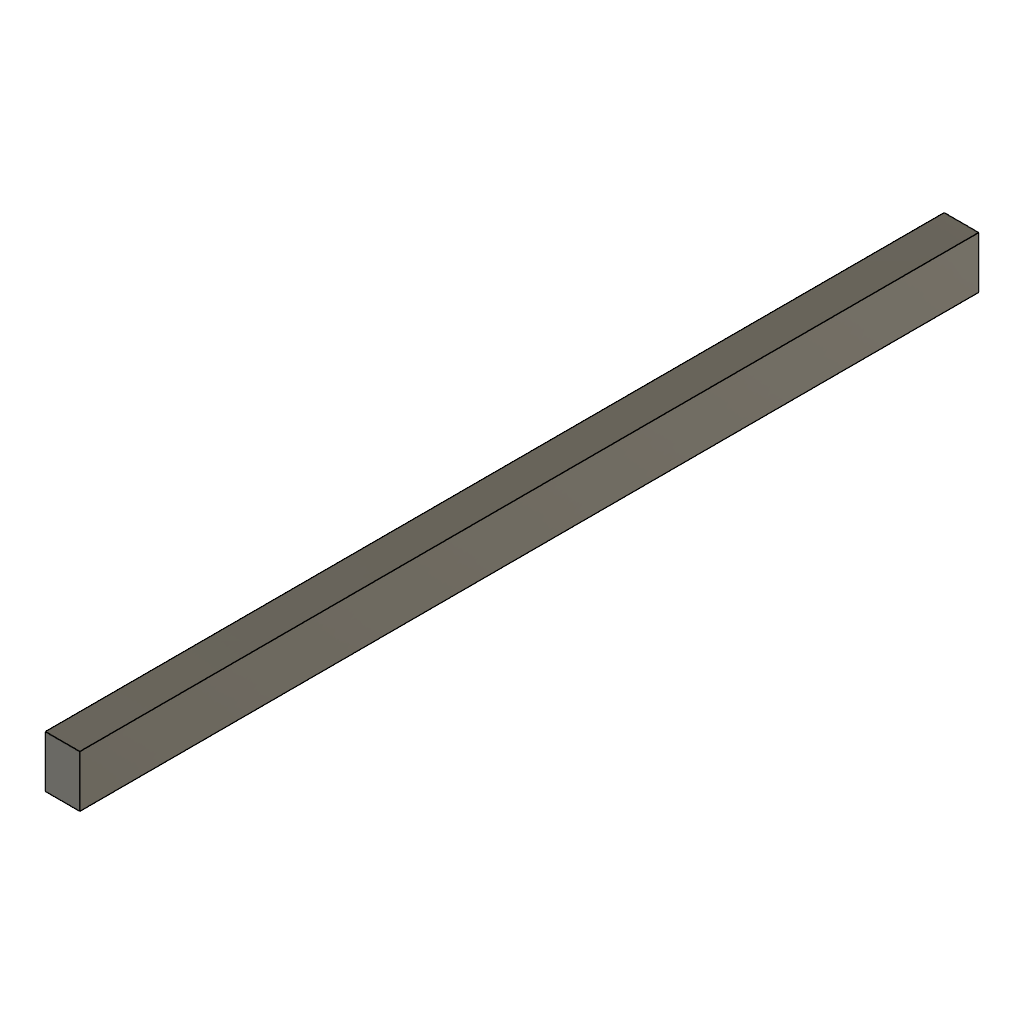
Fox Head Timing Belt Housing (Autodesk Fusion 360 archive; units mm, degrees)
design "side piece lock V2 (smaller)"
part number: 2026-11-04-11-16-01-376
Autodesk Fusion 360 part; units mm, degrees
sketch "Sketch1" plane through (0, 0, 0) normal (1, 0, 0) x (0, 1, 0)
  line L0 (0, 0) -> (104, 0)
  line L1 (104, 0) -> (104, 6)
  line L2 (104, 6) -> (0, 6)
  line L3 (0, 6) -> (0, 0)
  dimension "d1" = 6
  dimension "d2" = 104
  constraint horizontal L0
  constraint vertical L1
  constraint horizontal L2
  constraint vertical L3
  constraint coincident L0.start L3.end
  measures "d1" distance of L0.start L2.end
  measures "d2" distance of L1.end L2.end
extrude "Extrude1" add sketch "Sketch1" along normal blind 4
equation "d4 = 0deg 0'"

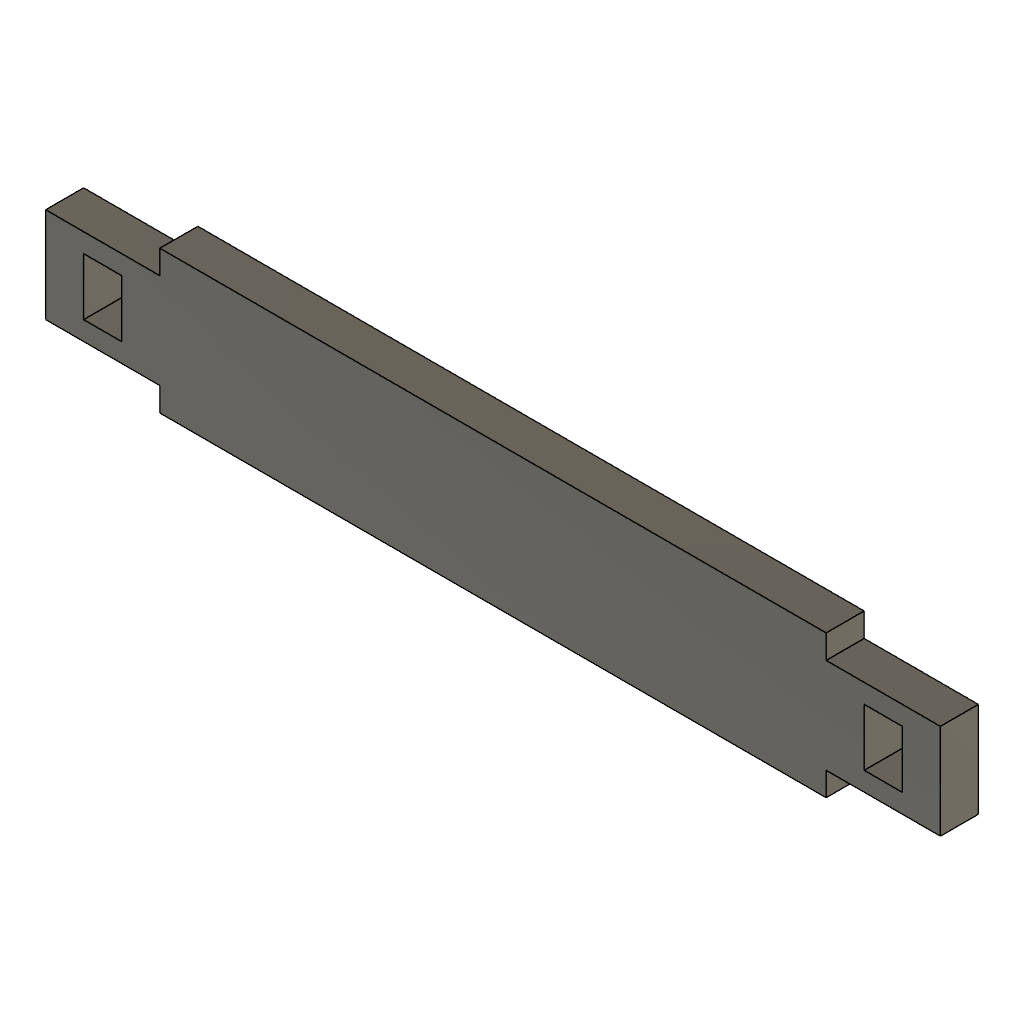
design "side piece connectors v2"
part number: 2026-11-04-10-45-29-765
Autodesk Fusion 360 part; units mm, degrees
sketch "Sketch1" plane through (0, 0, 0) normal (0, 1, 0) x (1, 0, 0)
  line L0 (12, -12.5) -> (82, -12.5)
  line L1 (82, 2.5) -> (12, 2.5)
  line L2 (12, -10) -> (0, -10)
  line L3 (0, -10) -> (0, 0)
  line L4 (0, 0) -> (12, 0)
  line L5 (4, -2) -> (8, -2)
  line L6 (8, -2) -> (8, -8)
  line L7 (8, -8) -> (4, -8)
  line L8 (4, -8) -> (4, -2)
  line L9 (82, -10) -> (94, -10)
  line L10 (86, -8) -> (90, -8)
  line L11 (90, -2) -> (86, -2)
  line L12 (86, -2) -> (86, -8)
  line L13 (90, -8) -> (90, -2)
  line L14 (94, -10) -> (94, 0)
  line L15 (94, 0) -> (82, 0)
  line L16 (12, 2.5) -> (12, 0)
  line L17 (12, -10) -> (12, -12.5)
  line L18 (82, -12.5) -> (82, -10)
  line L19 (82, 0) -> (82, 2.5)
  point P0 (4, -5)
  point P1 (94, -5)
  point P2 (90, -5)
  point P3 (94, 0)
  dimension "d1" = 70
  dimension "d2" = 12
  dimension "d3" = 4
  dimension "d5" = 15
  dimension "d6" = 10
  dimension "d7" = 6
  constraint horizontal L0
  constraint vertical L18
  constraint horizontal L1
  constraint vertical L16
  constraint horizontal L2
  constraint vertical L3
  constraint horizontal L4
  constraint horizontal L5
  constraint vertical L6
  constraint horizontal L7
  constraint vertical L8
  constraint midpoint L8 P0
  constraint coincident L3.end L4.start
  constraint collinear L16 L17
  constraint collinear L18 L19
  measures "d1" distance of L1.start L1.end
  measures "d2" distance of L2.start L2.end
  measures "d3" distance of L6.end L7.end
  measures "d5" distance of L0 L1
  measures "d6" distance of L2.end L3.end
  measures "d7" distance of L5.start L7.end
extrude "Extrude1" add sketch "Sketch1" along normal blind 4
equation "d14 = 0deg 0'"

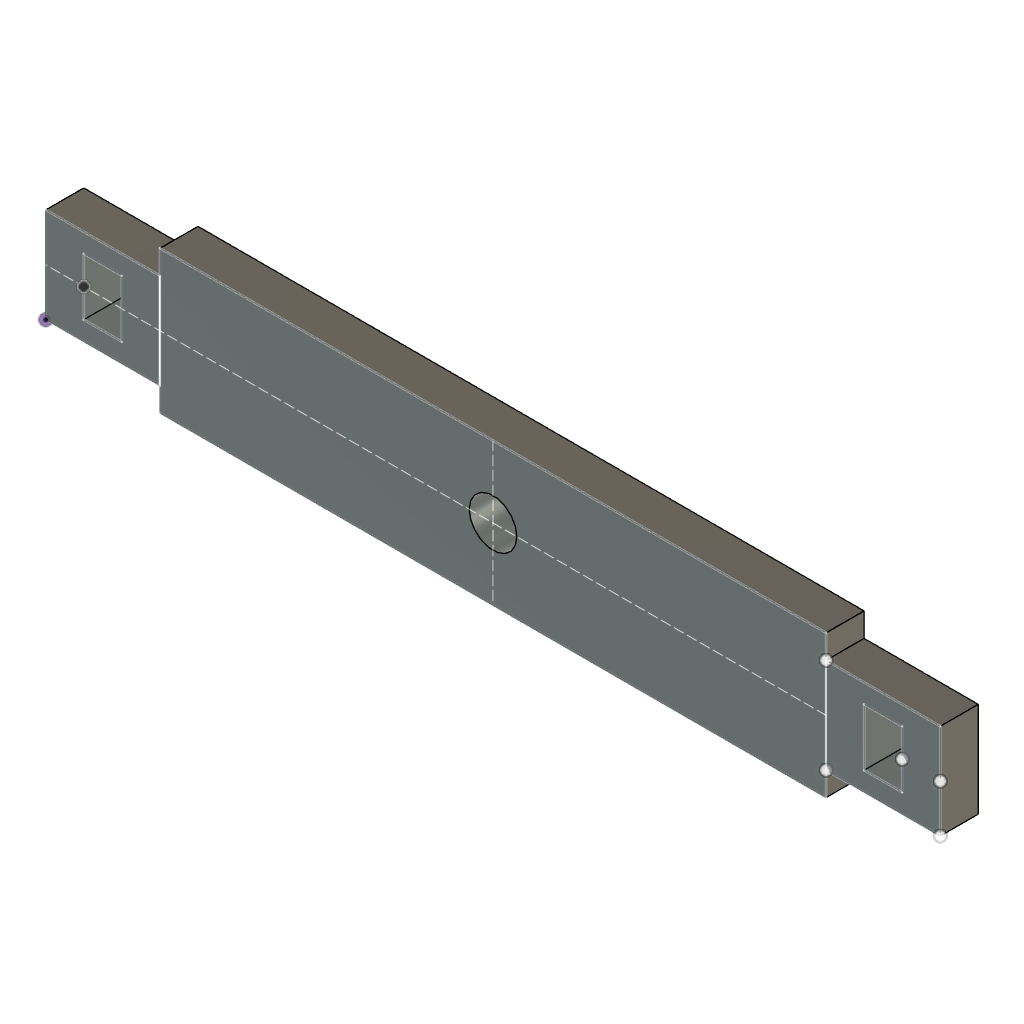
design "side piece dowel holders v2"
part number: 2026-11-04-10-45-29-765
Autodesk Fusion 360 part; units mm, degrees
sketch "Sketch1" plane through (0, 0, 0) normal (0, 1, 0) x (1, 0, 0)
  line L0 (12, -12.5) -> (82, -12.5)
  line L1 (82, -12.5) -> (82, 2.5)
  line L2 (82, 2.5) -> (12, 2.5)
  line L3 (12, 2.5) -> (12, -12.5)
  line L4 (12, -10) -> (0, -10)
  line L5 (0, -10) -> (0, 0)
  line L6 (0, 0) -> (12, 0)
  line L7 (12, 0) -> (12, -10)
  line L8 (4, -2) -> (8, -2)
  line L9 (8, -2) -> (8, -8)
  line L10 (8, -8) -> (4, -8)
  line L11 (4, -8) -> (4, -2)
  line L12 (82, -5) -> (0, -5) construction
  line L13 (47, -12.5) -> (47, 2.5) construction
  line L14 (82, -10) -> (94, -10)
  line L15 (86, -8) -> (90, -8)
  line L16 (90, -2) -> (86, -2)
  line L17 (86, -2) -> (86, -8)
  line L18 (90, -8) -> (90, -2)
  line L19 (94, -10) -> (94, 0)
  line L20 (94, 0) -> (82, 0)
  point P0 (4, -5)
  point P1 (94, -5)
  point P2 (90, -5)
  point P3 (94, 0)
  dimension "d1" = 70
  dimension "d2" = 12
  dimension "d3" = 4
  dimension "d5" = 15
  dimension "d6" = 10
  dimension "d7" = 6
  dimension "d12" = 4
  constraint horizontal L0
  constraint vertical L1
  constraint horizontal L2
  constraint vertical L3
  constraint horizontal L4
  constraint vertical L5
  constraint horizontal L6
  constraint vertical L7
  constraint coincident L3 L4.start
  constraint horizontal L8
  constraint vertical L9
  constraint horizontal L10
  constraint vertical L11
  constraint midpoint L1 L12.start
  constraint midpoint L5 L12.end
  constraint parallel L0 L12
  constraint midpoint L11 P0
  constraint coincident L12 P0
  constraint coincident L5.end L6.start
  constraint midpoint L0 L13.start
  constraint midpoint L2 L13.end
  constraint symmetric L5.end L13 P3
  constraint symmetric L4.start L13 L14.start
  constraint symmetric L4.end L13 L14.end
  constraint symmetric L6.end L13 L20.end
  constraint symmetric L8.start L13 L16.start
  constraint symmetric L8.end L13 L16.end
  constraint symmetric L9.end L13 L15.start
  constraint symmetric L10.end L13 L15.end
  constraint symmetric L12.end L13 P1
  constraint symmetric P0 L13 P2
  measures "d1" distance of L1.end L2.end
  measures "d2" distance of L4.start L4.end
  measures "d3" distance of L9.end L10.end
  measures "d5" distance of L0 L2
  measures "d6" distance of L4.end L5.end
  measures "d7" distance of L8.start L10.end
  measures "d12" distance of L7 L9
extrude "Extrude1" add sketch "Sketch1" along normal blind 4
sketch "Sketch2" plane through (0, 0, 0) normal (0, -1, 0) x (1, 0, 0)
  line L0 (4, 8) -> (8, 8)
  line L1 (8, 8) -> (8, 2)
  line L2 (8, 2) -> (4, 2)
  line L3 (4, 2) -> (4, 8)
  line L4 (90, 8) -> (90, 2)
  line L5 (90, 2) -> (86, 2)
  line L6 (86, 2) -> (86, 8)
  line L7 (86, 8) -> (90, 8)
  line L8 (12, 12.5) -> (12, 10)
  line L9 (12, 10) -> (0, 10)
  line L10 (0, 10) -> (0, 0)
  line L11 (0, 0) -> (12, 0)
  line L12 (12, 0) -> (12, -2.5)
  line L13 (12, -2.5) -> (82, -2.5)
  line L14 (82, -2.5) -> (82, 0)
  line L15 (82, 0) -> (94, 0)
  line L16 (94, 0) -> (94, 10)
  line L17 (94, 10) -> (82, 10)
  line L18 (82, 10) -> (82, 12.5)
  line L19 (82, 12.5) -> (12, 12.5)
  circle A0 centre (47, 5) radius 2.5
  dimension "d15" = 5
  measures "d15" diameter of A0
extrude "Extrude2" cut sketch "Sketch2" against normal up to surface (4 mm away) contours A0
equation "d14 = 0deg 0'"
equation "d17 = 0deg 0'"
